711005_P01_ELECTRICAL-HUB-ZONE-COVER-PLATE_CAD (Autodesk Fusion 360 design; units mm, degrees)
description: ELECTRICAL - HUB ZONE COVER PLATE | Điện - mặt che vùng cảm biến | P01
part number: 711005
Autodesk Fusion 360 part; units mm, degrees
sketch "OUTLINE AND CUT-OUTS - HUB" plane through (0, 0, 0) normal (0, 0, 1) x (1, 0, 0) in component "711005 ELECTRICAL - HUB ZONE COVER PLATE"
  line L0 (0, 0) -> (180, 0)
  line L1 (180, 0) -> (180, 180)
  line L2 (180, 180) -> (0, 180)
  line L3 (0, 180) -> (0, 0)
  line L4 (30, 90) -> (150, 90)
  line L5 (150, 90) -> (150, 160)
  line L6 (150, 160) -> (30, 160)
  line L7 (30, 160) -> (30, 90)
  circle A0 centre (35, 50) radius 8.1
  circle A1 centre (75, 50) radius 8.1
  circle A2 centre (115, 50) radius 8.1
  circle A3 centre (150, 50) radius 3.75
  circle A4 centre (10, 10) radius 2.25
  circle A5 centre (170, 10) radius 2.25
  circle A6 centre (10, 170) radius 2.25
  circle A7 centre (170, 170) radius 2.25
  dimension "d47" = 180
  dimension "d48" = 180
  dimension "d49" = 120
  dimension "d50" = 70
  dimension "d51" = 30
  dimension "d52" = 90
  dimension "d53" = 16.2
  dimension "d54" = 35
  dimension "d55" = 50
  dimension "d56" = 16.2
  dimension "d57" = 75
  dimension "d58" = 50
  dimension "d59" = 16.2
  dimension "d60" = 115
  dimension "d61" = 50
  dimension "d62" = 7.5
  dimension "d63" = 150
  dimension "d64" = 50
  dimension "d65" = 4.5
  dimension "d66" = 10
  dimension "d67" = 10
  dimension "d68" = 4.5
  dimension "d69" = 170
  dimension "d70" = 10
  dimension "d71" = 4.5
  dimension "d72" = 10
  dimension "d73" = 170
  dimension "d74" = 4.5
  dimension "d75" = 170
  dimension "d76" = 170
  constraint horizontal L0
  constraint vertical L1
  constraint horizontal L2
  constraint vertical L3
  constraint vertical L0.start L3.end
  constraint horizontal L0.start L3.end
  constraint horizontal L4
  constraint vertical L5
  constraint horizontal L6
  constraint vertical L7
  measures "d47" horizontal distance of L0.start L0.end
  measures "d48" vertical distance of L0.start L2.end
  measures "d49" horizontal distance of L4.start L4.end
  measures "d50" vertical distance of L4.start L6.end
  measures "d51" horizontal distance of L0.start L4.start
  measures "d52" vertical distance of L0.start L4.start
  measures "d53" diameter of A0
  measures "d54" horizontal distance of L0.start A0.centre
  measures "d55" vertical distance of L0.start A0.centre
  measures "d56" diameter of A1
  measures "d57" horizontal distance of L0.start A1.centre
  measures "d58" vertical distance of L0.start A1.centre
  measures "d59" diameter of A2
  measures "d60" horizontal distance of L0.start A2.centre
  measures "d61" vertical distance of L0.start A2.centre
  measures "d62" diameter of A3
  measures "d63" horizontal distance of L0.start A3.centre
  measures "d64" vertical distance of L0.start A3.centre
  measures "d65" diameter of A4
  measures "d66" horizontal distance of L0.start A4.centre
  measures "d67" vertical distance of L0.start A4.centre
  measures "d68" diameter of A5
  measures "d69" horizontal distance of L0.start A5.centre
  measures "d70" vertical distance of L0.start A5.centre
  measures "d71" diameter of A6
  measures "d72" horizontal distance of L0.start A6.centre
  measures "d73" vertical distance of L0.start A6.centre
  measures "d74" diameter of A7
  measures "d75" horizontal distance of L0.start A7.centre
  measures "d76" vertical distance of L0.start A7.centre
extrude "EXTRUDE - PLATE HUB" add sketch "OUTLINE AND CUT-OUTS - HUB" along normal blind 1.5 in component "711005 ELECTRICAL - HUB ZONE COVER PLATE"
component "711005 ELECTRICAL - HUB ZONE COVER PLATE" placed x (1, 0, 0) y (0, 1, 0) z (0, 0, 1) at (0, 0, 0)
equation "t = 1.5 mm" comment "PROPOSED: 5052-H32 aluminium 1.5 mm, black anodised AA20 (D-67)"
equation "w = 180.0 mm" comment "DECIDED: D-61, D-70: the 180 x 180 zone"
equation "h = 180.0 mm" comment "DECIDED: D-61, D-70"
equation "win_w = 120 mm" comment "HOLD: hub window width: the hub's size (ISS-060)"
equation "win_h = 70 mm" comment "HOLD: hub window height (ISS-060)"
equation "win_zc = 125 mm" comment "ASSUMPTION: hub window centre from the bottom edge"
equation "btn_d = 16.2 mm" comment "HOLD: 16 mm panel push button hole (button SKU HOLD)"
equation "btn_p = 40 mm" comment "ASSUMPTION: button pitch (BOOST, TEST, CALL)"
equation "btn_zc = 50 mm" comment "ASSUMPTION: button row centre from the bottom edge"
equation "btn_x1 = 35 mm" comment "ASSUMPTION: first button centre from the left edge: at least 2 diameters (32.4) from the edge (C09)"
equation "knob_d = 7.5 mm" comment "HOLD: potentiometer bush hole (part HOLD)"
equation "knob_x = 150 mm" comment "ASSUMPTION: LIGHT knob centre from the left edge"
equation "screw_d = 4.5 mm" comment "HOLD: M4 fixing holes into the column (CEILING models the column)"
equation "screw_e = 10 mm" comment "ASSUMPTION: fixing hole centre from each corner"
equation "d47 = ( w ) - ( 0 mm )"
equation "d48 = ( h ) - ( 0 mm )"
equation "d49 = ( w / 2 + win_w / 2 ) - ( w / 2 - win_w / 2 )"
equation "d50 = ( win_zc + win_h / 2 ) - ( win_zc - win_h / 2 )"
equation "d51 = abs(w / 2 - win_w / 2)"
equation "d52 = abs(win_zc - win_h / 2)"
equation "d53 = btn_d"
equation "d54 = abs(btn_x1 + 0 * btn_p)"
equation "d55 = abs(btn_zc)"
equation "d56 = btn_d"
equation "d57 = abs(btn_x1 + 1 * btn_p)"
equation "d58 = abs(btn_zc)"
equation "d59 = btn_d"
equation "d60 = abs(btn_x1 + 2 * btn_p)"
equation "d61 = abs(btn_zc)"
equation "d62 = knob_d"
equation "d63 = abs(knob_x)"
equation "d64 = abs(btn_zc)"
equation "d65 = screw_d"
equation "d66 = abs(screw_e)"
equation "d67 = abs(screw_e)"
equation "d68 = screw_d"
equation "d69 = abs(w - screw_e)"
equation "d70 = abs(screw_e)"
equation "d71 = screw_d"
equation "d72 = abs(screw_e)"
equation "d73 = abs(h - screw_e)"
equation "d74 = screw_d"
equation "d75 = abs(w - screw_e)"
equation "d76 = abs(h - screw_e)"
equation "d77 = t"
named bodies: "ELECTRICAL - HUB ZONE COVER PLATE"
